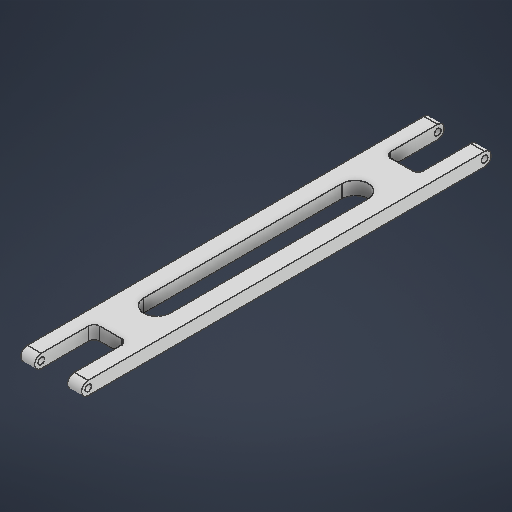
# Autodesk Inventor part: barraBrazo1
Saved by Autodesk Inventor 2027.1 (Build 311270010, 270A)
## iProperties
Created: 2026-11-02
Part Number: barraBrazo1
Material: Genérico
Document SubType Name: Modeling
Designer: MANGEL
Density: 1 g/cm^3
Appearance: Valor por defecto
Author: MANGEL
Autodesk Inventor part; units mm, degrees
ref_plane "YZ Plane" through (0, 0, 0) normal (1, 0, 0) x (0, 1, 0)
ref_plane "XZ Plane" through (0, 0, 0) normal (0, 1, 0) x (-1, 0, 0)
ref_plane "XY Plane" through (0, 0, 0) normal (0, 0, 1) x (1, 0, 0)
sketch "Boceto2" plane through (0, 0, 0) normal (1, 0, 0) x (0, 1, 0)
  line L0 (0, 150) -> (0, -150) construction
  line L1 (-5, 150) -> (-5, -150)
  line L2 (5, -150) -> (5, 150)
  arc A0 (5, 150) -> (-5, 150) centre (0, 150) ccw
  arc A1 (-5, -150) -> (5, -150) centre (0, -150) ccw
  point P0 (0, 0)
  dimension "d4" = 10
  dimension "d5" = 300
  constraints: 8 end point, 4 point on circle, 4 tangent, 2 centre point, 1 midpoint, 1 parallel, 1 vertical
  measures "d4" distance between parallel lines of L1 L2
  measures "d5" distance of L2.start L2.end
extrude "Extrusión2" add sketch "Boceto2" along normal blind 46
sketch "Boceto3" plane through (0, 5, 150) normal (0, 1, 0) x (1, 0, 0)
  line L0 (23, 75) -> (23, 225) construction
  line L1 (33, 75) -> (33, 225)
  line L2 (13, 225) -> (13, 75)
  arc A0 (13, 75) -> (33, 75) centre (23, 75) ccw
  arc A1 (33, 225) -> (13, 225) centre (23, 225) ccw
  line L3 (0, 300) -> (0, 0) projected
  line L4 (0, 300) -> (46, 300) projected
  line L5 (10.5, 300) -> (35.5, 300)
  line L6 (35.5, 300) -> (35.5, 264)
  line L7 (31.5, 260) -> (14.5, 260)
  line L8 (10.5, 264) -> (10.5, 300)
  line L9 (23, 150) -> (46, 150) construction
  line L10 (46, 300) -> (46, 0) construction
  arc A2 (10.5, 264) -> (14.5, 260) centre (14.5, 264) ccw
  arc A3 (31.5, 260) -> (35.5, 264) centre (31.5, 264) ccw
  line L11 (10.5, 0) -> (35.5, 0)
  line L12 (35.5, 0) -> (35.5, 36)
  line L13 (31.5, 40) -> (14.5, 40)
  line L14 (10.5, 36) -> (10.5, 0)
  arc A4 (14.5, 40) -> (10.5, 36) centre (14.5, 36) ccw
  arc A5 (35.5, 36) -> (31.5, 40) centre (31.5, 36) ccw
  line L15 (0, 305) -> (46, 305) projected
  line L16 (10.5, 300) -> (35.5, 300)
  line L17 (35.5, 300) -> (35.5, 305)
  line L18 (35.5, 305) -> (10.5, 305)
  line L19 (10.5, 305) -> (10.5, 300)
  line L20 (10.5, 0) -> (35.5, 0)
  line L21 (35.5, 0) -> (35.5, -5)
  line L22 (35.5, -5) -> (10.5, -5)
  line L23 (10.5, -5) -> (10.5, 0)
  point P0 (0, 150)
  point P1 (0, 150)
  point P2 (23, 300)
  point P3 (10.5, 260)
  point P4 (23, 260)
  point P5 (23, 300)
  point P6 (23, 0)
  point P7 (10.5, 40)
  point P8 (23, 40)
  point P9 (23, 0)
  point P10 (10.5, 305)
  dimension "d8" = 20
  dimension "d9" = 150
  dimension "d10" = 25
  dimension "d11" = 40
  dimension "d12" = 4
  constraints: 42 end point, 12 point on circle, 12 symmetric about line, 8 tangent, 7 parallel, 6 centre point, 6 midpoint, 6 point on line, 3 horizontal, 3 perpendicular, 2 collinear, 2 vertical alignment, 1 equal radius, 1 horizontal alignment, 1 vertical, 2 other
  measures "d8" distance between parallel lines of L1 L2
  measures "d9" distance of L1.start L1.end
  measures "d10" distance between parallel lines of L6 L8
  measures "d11" distance of point (10.5, 260) L5.start
  measures "d12" radius of A2
extrude "Extrusión3" cut sketch "Boceto3" against normal through all
sketch "Boceto4" plane through (46, 0, 0) normal (1, 0, 0) x (0, 0, -1)
  arc A0 (-150, 5) -> (-150, -5) centre (-150, 0) ccw projected
  circle A1 centre (-150, 0) radius 2.5
  arc A2 (150, -5) -> (150, 5) centre (150, 0) ccw projected
  circle A3 centre (150, 0) radius 2.5
  point P0 (0, 0)
  dimension "d15" = 5
  dimension "d16" = 5
  constraints: 2 centre point, 2 coincident
  measures "d15" diameter of A1
  measures "d16" diameter of A3
extrude "Extrusión4" cut sketch "Boceto4" against normal through all
